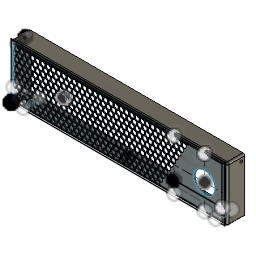
FacePlate Power Supply-Bunnings (Autodesk Fusion 360 design; units mm, degrees)
Autodesk Fusion 360 part; units mm, degrees
sketch "Sketch1" plane through (0, 0, 0) normal (0, 1, 0) x (1, 0, 0)
  line L0 (0, 0) -> (245, 0)
  line L1 (245, 0) -> (245, -63)
  line L2 (245, -63) -> (0, -63)
  line L3 (0, -63) -> (0, 0)
  line L4 (242, -60) -> (3, -60)
  line L5 (242, -3) -> (242, -60)
  line L6 (3, -3) -> (242, -3)
  line L7 (3, -60) -> (3, -3)
  line L8 (57.5, -36.4434) -> (60, -37.8868)
  line L9 (60, -37.8868) -> (62.5, -36.4434)
  line L10 (62.5, -36.4434) -> (62.5, -33.5566)
  line L11 (62.5, -33.5566) -> (60, -32.1132)
  line L12 (60, -32.1132) -> (57.5, -33.5566)
  line L13 (57.5, -33.5566) -> (57.5, -36.4434)
  line L14 (60, -35) -> (62.5, -35) construction
  line L15 (60, -35) -> (61.25, -37.1651) construction
  line L16 (3, -31.5) -> (242, -31.5) construction
  line L17 (222, -3) -> (222, -60) construction
  circle A0 centre (222, -31.5) radius 12
  line L18 (187, -3) -> (187, -60) construction
  line L19 (3, -16.5) -> (242, -16.5)
  circle A1 centre (187, -16.5) radius 5
  point P0 (60, -35)
  dimension "d1" = 245
  dimension "d2" = 63
  dimension "d12" = 2.5
  dimension "d19" = 20
  dimension "d20" = 24
  dimension "d21" = 35
  dimension "d22" = -15
  dimension "d23" = 10
  constraint horizontal L0
  constraint vertical L1
  constraint horizontal L2
  constraint vertical L3
  constraint coincident L0.start L3.end
  constraint coincident P0 L14.start
  constraint midpoint L9 L15.end
  constraint midpoint L7 L16.start
  constraint midpoint L5 L16.end
  constraint midpoint L17 A0.centre
  constraint coincident L19 A1.centre
  constraint coincident L18 A1.centre
  measures "d1" distance of L0.start L0.end
  measures "d2" distance of L0.start L2.end
  measures "d12" distance of P0 L13
  measures "d20" diameter of A0
  measures "d23" diameter of A1
extrude "Extrude1" add sketch "Sketch1" along normal blind 20 contours L0 L1 L2 L3 makes body 1
extrude "Extrude2" add sketch "Sketch1" along normal blind 1 separate body contours L4 L5 L7 L19 A1 | L5 L6 L7 L19 A1 | L19 A1 | L19 A1 | L8 L9 L10 L11 L12 L13 | A0 makes body 2
extrude "Extrude3" cut sketch "Sketch1" along normal blind 1 contours L8 L9 L10 L11 L12 L13 bodies 2
pattern_linear "R-Pattern1" count 13 spacing 6 along (0.5, 0, 0.866025) both ways count 42 spacing 6 along (1, 0, 0) both ways of "Extrude3"
extrude "Extrude4" cut sketch "Sketch1" along normal blind 2 contours L19 A1 | L19 A1 | A0 bodies 2
fillet "Fillet1" radius 2 1 edges at (122.5, 0, 0) on bodies 1
fillet "Fillet2" radius 2 3 edges at (245, 11, 0) (245, 0.5858, 0.5858) (245, 0, 32.5) on bodies 1
fillet "Fillet3" radius 2 3 edges at (245, 11, 63) (244.4142, 0.5858, 63) (121.5, 0, 63) on bodies 1
fillet "Fillet4" radius 2 5 edges at (0, 11, 63) (0, 0.5858, 62.4142) (0, 0, 31.5) (0, 0.5858, 0.5858) (0, 11, 0) on bodies 1
sketch "Sketch3" plane through (0, 0, 0) normal (0, 0, -1) x (1, 0, 0)
  line L0 (2, -2) -> (2, -20)
  line L1 (2, -20) -> (243, -20)
  line L2 (243, -20) -> (243, -2)
  line L3 (243, -2) -> (2, -2)
  line L4 (2, -11) -> (243, -11) construction
  line L5 (122.5, -11) -> (122.5, -20) construction
  circle A0 centre (122.5, -11) radius 1.5
  line L6 (12, -2) -> (12, -20) construction
  line L7 (233, -20) -> (233, -2) construction
  circle A1 centre (12, -11) radius 1.5
  circle A2 centre (233, -11) radius 1.5
  dimension "d34" = 3
  dimension "d35" = -10
  dimension "d36" = -10
  dimension "d37" = 3
  dimension "d38" = 3
  constraint midpoint L0 L4.start
  constraint midpoint L2 L4.end
  constraint midpoint L4 L5.start
  constraint midpoint L1 L5.end
  constraint coincident L5.start A0.centre
  constraint midpoint L6 A1.centre
  constraint midpoint L7 A2.centre
  measures "d34" diameter of A0
  measures "d37" diameter of A1
  measures "d38" diameter of A2
extrude "Extrude5" cut sketch "Sketch3" against normal blind 3 contours A0 | A1 | A2 bodies 1
sketch "Sketch5" plane through (0, 0, 0) normal (-1, 0, 0) x (0, -1, 0)
  line L0 (-2, 61) -> (-20, 61)
  line L1 (-20, 61) -> (-20, 2)
  line L2 (-20, 2) -> (-2, 2)
  line L3 (-2, 2) -> (-2, 61)
  line L4 (-16, 61) -> (-16, 2) construction
  line L5 (-2, 57) -> (-20, 57) construction
  circle A0 centre (-16, 57) radius 1.5
  dimension "d41" = -4
  dimension "d42" = -4
  dimension "d43" = 3
  constraint coincident L5 A0.centre
  constraint coincident L4 A0.centre
  measures "d43" diameter of A0
extrude "Extrude6" cut sketch "Sketch5" against normal blind 300 contours A0 bodies 1
delete_face "DeleteFace1" 1 faces at (244.0918, 0.3448, 61.2611) on bodies 1
delete_face "DeleteFace2" 1 faces at (243.2611, 0.9082, 0.3448) on bodies 1
delete_face "DeleteFace3" 1 faces at (244.9885, 1.7859, 21.6272) on bodies 1
delete_face "DeleteFace4" 1 faces at (243.222, 7.8735, 62.9876) on bodies 1
delete_face "DeleteFace5" 1 faces at (244.9931, 13.3371, 1.8343) on bodies 1
extrude "Extrude7" add 1 faces at (245, 11.9626, 19.1681) along direction (1, 0, 0) blind 3 on bodies 1 bodies 1
fillet "Fillet5" radius 2 5 edges at (248, 11, 63) (248, 0.5858, 62.4142) (248, 0, 31.5) (248, 0.5858, 0.5858) (248, 11, 0) on bodies 1
extrude "Extrude8" cut 1 faces at (242, 11.8887, 20.5125) along direction (1, 0, 0) blind 3 on bodies 1 bodies 1
extrude "Extrude9" add 1 faces at (242, 0.3333, 22) along direction (1, 0, 0) blind 3 on bodies 2 bodies 1 2
